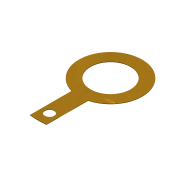
# Autodesk Inventor part: carbonpath m
Saved by Autodesk Inventor 2015 SP1 (Build 190203100, 203)
## iProperties
Created: 2015-06-26
Part Number: carbonpath m
Material: Generic
Document SubType Name: Modeling
Designer: Peter Mulkers
Density: 1 g/cm^3
Appearance: Weld - Brass
Author: Peter Mulkers
Autodesk Inventor part; units mm, degrees
ref_plane "YZ Plane" through (0, 0, 0) normal (1, 0, 0) x (0, 1, 0)
ref_plane "XZ Plane" through (0, 0, 0) normal (0, 1, 0) x (-1, 0, 0)
ref_plane "XY Plane" through (0, 0, 0) normal (0, 0, 1) x (1, 0, 0)
sketch "Sketch1" plane through (0, 0, 0) normal (0, 0, 1) x (1, 0, 0)
  arc A0 (1.75, -6.5192) -> (-1.75, -6.5192) centre (0, 0) ccw
  line L0 (-1.75, -6.5192) -> (-1.75, -15.4009)
  line L1 (1.75, -6.5192) -> (1.75, -15.4009)
  arc A1 (-1.75, -15.4009) -> (1.75, -15.4009) centre (0, 0) ccw
  circle A2 centre (0, -13) radius 1
  circle A3 centre (0, 0) radius 4.25
  point P0 (0, -15.5)
  dimension "d9" = 13.5
  dimension "d11" = 1.75
  dimension "d12" = 1.75
  dimension "d14" = 15.5
  dimension "d15" = 2
  dimension "d16" = 13
  dimension "d17" = 8.5
  dimension "d18" = 15.5
  constraints: 5 point on circle, 4 centre point, 4 end point, 3 coincident, 2 vertical, 2 vertical alignment, 1 concentric
  measures "d9" diameter of A0
  measures "d11" distance from line of point (0, 0) L0
  measures "d12" distance from line of L1 point (0, 0)
  measures "d14" radius of A1
  measures "d15" diameter of A2
  measures "d16" distance of point (0, 0) A2.centre
  measures "d17" diameter of A3
  measures "d18" distance of point (0, 0) L1.end
extrude "Extrusion1" add sketch "Sketch1" along normal blind 0.1
body "Solid1"
